handle-sleeve_v0.1 (Autodesk Fusion 360 design; units mm, degrees)
part number: 2026-11-10-01-16-06-730
Autodesk Fusion 360 part; units mm, degrees
ref_plane "WorkPlane1" through (0, 0, 95) normal (0, 0, 1) x (1, 0, 0)
sketch "Outer" plane through (0, 0, 0) normal (0, 0, 1) x (1, 0, 0)
  circle A0 centre (0, 0) radius 18.75
  dimension "d12" = 37.5
  constraint coincident A0.centre origin
  measures "d12" diameter of A0
extrude "GripBody" add sketch "Outer" along normal blind 95
fillet "TopComfortFillet" radius 3 1 edges at (-17.4811, -6.7803, 95)
chamfer "BaseChamfer" distance 1 angle 45 1 edges at (-17.4811, -6.7803, 0) tangent chain off
sketch "BoreBottom" plane through (0, 0, 0) normal (0, 0, 1) x (1, 0, 0)
  circle A0 centre (0, 0) radius 3.2
  dimension "d18" = 6.4
  constraint coincident A0.centre origin
  measures "d18" diameter of A0
sketch "BoreTop" plane through (0, 0, 95) normal (0, 0, 1) x (1, 0, 0)
  circle A0 centre (0, 0) radius 10
  dimension "d19" = 20
  constraint coincident A0.centre origin
  measures "d19" diameter of A0
loft "TaperedBore" cut profiles "BoreBottom", "BoreTop" section 1 section 2
sketch "SlotBottom" plane through (0, 0, 0) normal (0, 0, 1) x (1, 0, 0)
  line L0 (-6, -1.75) -> (6, -1.75)
  line L1 (6, -1.75) -> (6, 1.75)
  line L2 (6, 1.75) -> (-6, 1.75)
  line L3 (-6, 1.75) -> (-6, -1.75)
  line L4 (-6, -1.75) -> (6, 1.75) construction
  dimension "d20" = 12
  dimension "d21" = 3.5
  constraint horizontal L0
  constraint vertical L1
  constraint horizontal L2
  constraint vertical L3
  constraint midpoint origin L4
  measures "d20" horizontal distance of L0.start L0.end
  measures "d21" vertical distance of L0.end L1.end
sketch "SlotTop" plane through (0, 0, 95) normal (0, 0, 1) x (1, 0, 0)
  line L0 (-12, -1.75) -> (12, -1.75)
  line L1 (12, -1.75) -> (12, 1.75)
  line L2 (12, 1.75) -> (-12, 1.75)
  line L3 (-12, 1.75) -> (-12, -1.75)
  line L4 (-12, -1.75) -> (12, 1.75) construction
  dimension "d22" = 24
  dimension "d23" = 3.5
  constraint horizontal L0
  constraint vertical L1
  constraint horizontal L2
  constraint vertical L3
  constraint midpoint origin L4
  measures "d22" horizontal distance of L0.start L0.end
  measures "d23" vertical distance of L0.end L1.end
loft "FlatHandleSlot" cut profiles "SlotBottom", "SlotTop" section 1 section 2
equation "grip_dia = 37.5 mm" comment "Outer grip diameter = 0.197 x hand length (Kong & Lowe 2005); M = ANSUR II combined P50 hand length 189.5 mm"
equation "grip_len = 95 mm" comment "Sleeve length = hand breadth + ~8 mm; M = ANSUR II combined P50 hand breadth 86 mm"
equation "bore_top_dia = 20 mm" comment "Bore entry diameter = largest commercial foam-tubing bore (13/16 in)"
equation "bore_bot_dia = 6.4 mm" comment "Bore exit diameter = smallest commercial foam-tubing bore (1/4 in)"
equation "slot_w_top = min(24 mm; grip_dia - 2 * ( top_fillet + 3 mm ))" comment "Slot width at entry: 24 mm (design estimate) capped so >= 3 mm wall remains under the top fillet"
equation "slot_w_bot = 12 mm" comment "Flat-handle slot width at exit (design estimate)"
equation "slot_t = 3.5 mm" comment "Flat-handle slot thickness (design estimate)"
equation "top_fillet = 3 mm" comment "Comfort fillet on top rim"
equation "base_chamfer = 1 mm" comment "45 deg chamfer on bed edge (printability)"
equation "d10 = grip_len"
equation "d12 = grip_dia"
equation "d13 = grip_len"
equation "d16 = top_fillet"
equation "d17 = base_chamfer"
equation "d18 = bore_bot_dia"
equation "d19 = bore_top_dia"
equation "d20 = slot_w_bot"
equation "d21 = slot_t"
equation "d22 = slot_w_top"
equation "d23 = slot_t"
named bodies: "HandleSleeve"
